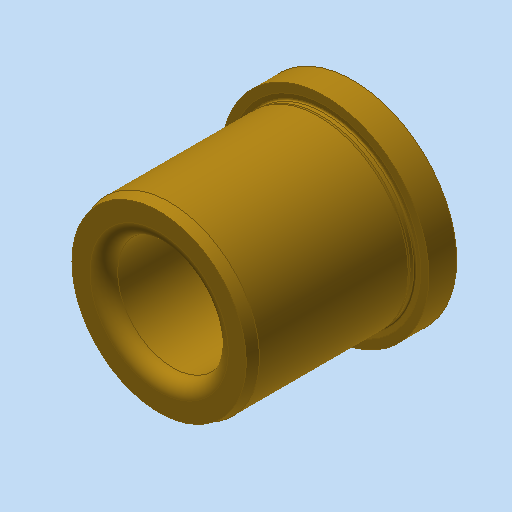
# Autodesk Inventor part: MM0867AN150_G02_111
Saved by Autodesk Inventor 2023.3 (Build 273359000, 359)
## iProperties
Created: 2020-01-15
Part Number: MM0867AN150_G02_111
Material: Generisch
Catalog Web Link: www.cadenas.de
Description: =<RBPARTNOTITLE2>
Vendor: NORELEM
Document SubType Name: Modeling
Designer: psadmin
Manufacturer: NORELEM
Mass: 9.81413 g
Surface Area: 46.5381 cm^2
Volume: 9.81413 cm^3
Density: 1 g/cm^3
Appearance: gold AnP
Category: PARTsolutions
Company: NORELEM
PSOL_IDENT_0: {$CADENAS_DATA\23d-libs\norelem\data\08000\08910.prj},172 {VTYP=3D},{NB=08910-B1600X28},{LINA=08910-
PSOL_IDENT_1: B1600X28},{NN=08910},{DATE=19.12.2019 14:43:44},{GEOMDATE=18.12.2019 13:22:13},{VERSION=v1},{LINEID=
PSOL_IDENT_2: 47990},{WBVAR=},{WBNUMERIC=}  {NB=08910-B1600X28},{LINA=08910-B1600X28},{KT=B},{BEST=08910-B1600X28}
PSOL_IDENT_3: ,{FORM=B},{D1=16.0},{D2=26},{D3=30},{L1=28},{AUSF=mittel},{L2=4.0},{R=2.0},{T1=0.02},{T2=0.03},{BS=I
PSOL_IDENT_4: nfotext},{FILTER=NORELEM,KIPP},{XA=1.500},{ZGT=Einführfase oder Zentrieransatz},{ZGTX=Chamfer for in
PSOL_IDENT_5: sert},{GEW=0,0757},{ZTN=84661038},{EAN=4059495203553},{ROHS=Yes}
NN: 08910
NT: Drill bushes with collar DIN 172
NB: 08910-B1600X28
NBSYN: $BEST.
LINA: 08910-B1600X28
BEST: 08910-B1600X28
FORM: B
D1: 16
D2: 26
D3: 30
L1: 28
AUSF: medium
L2: 4
R: 2
T1: 0.02
T2: 0.03
BS: Infotext
GEW: 0,0757
ZTN: 84661038
EAN: 4059495203553
ROHS: Yes
SUPPLIER: NORELEM
ARTICLENO: 08910-B1600X28
BOMINFO: 08910-B1600X28
CREATOR: CADENAS GmbH
RBPARTNOTITLE1: drill bushes with collar DIN179
AnP_Kategorie: 2
AnP_Material: =<Material>
RBDRAWINGMISSINGSPEC: --
RBPARTMADEOF: 08910-B1600X28
RBPARTNOTITLE2: Bohrbuchse mit Bund DIN 179
RBMATERIAL: --
RBSURFACE2: Drill bushes with collar DIN 172
RBMATNO: =<Part Number>
Title: 08910-B1600X28
Author: Cadenas PARTsolutions
Comments: =<RBSURFACE2>
Keywords: =<RBPARTMADEOF>
Revision Number: 01
Autodesk Inventor part; units mm, degrees
ref_plane "YZ Plane" through (0, 0, 0) normal (1, 0, 0) x (0, 1, 0)
ref_plane "XZ Plane" through (0, 0, 0) normal (0, 1, 0) x (-1, 0, 0)
ref_plane "XY Plane" through (0, 0, 0) normal (0, 0, 1) x (1, 0, 0)
sketch "Sketch_1" plane through (0, 0, 0) normal (0, 0, 1) x (1, 0, 0)
  line L0 (0, 0) -> (0, 28)
  line L1 (8, 26) -> (8, 2)
  arc A0 (8, 2) -> (10, 0) centre (10, 2) ccw
  line L2 (10, 0) -> (13, 0)
  line L3 (13, 0) -> (13, 23)
  line L4 (13, 23) -> (12.9, 23.3732)
  line L5 (12.9, 23.3732) -> (12.9, 23.8964)
  arc A1 (13.1278, 24.0945) -> (12.9, 23.8964) centre (13.1, 23.8964) ccw
  line L6 (13.1278, 24.0945) -> (13.8, 24)
  line L7 (13.8, 24) -> (15, 24)
  line L8 (15, 24) -> (15, 28)
  line L9 (15, 28) -> (10, 28)
  arc A2 (10, 28) -> (8, 26) centre (10, 26) ccw
  constraints: 20 end point, 6 point on circle, 3 centre point
revolve "Revolution1" add sketch "Sketch_1" angle 360 about axis through (0, 0, 0) along (0, 1, 0)
sketch "Sketch_2" plane through (0, 0, 0) normal (0, 0, 1) x (1, 0, 0)
  line L0 (0, 0) -> (0, 1.5)
  line L1 (12.5981, 0) -> (18, 0)
  line L2 (18, 0) -> (18, 1.5)
  line L3 (18, 1.5) -> (13, 1.5)
  line L4 (13, 1.5) -> (12.5981, 0)
  constraints: 10 end point
revolve "Revolution2" cut sketch "Sketch_2" angle 360 about axis through (0, 0, 0) along (0, -1, 0)
body "Solid1"
